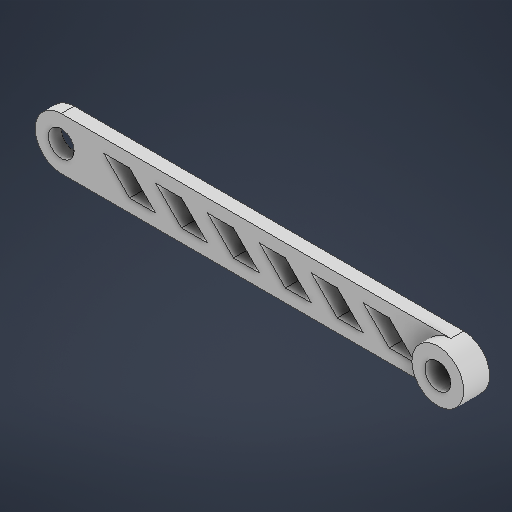
# Autodesk Inventor part: link2
Saved by Autodesk Inventor 2026.1 (Build 301233020, 233B)
## iProperties
Created: 2026-04-08
Part Number: link2
Material: Generic
Document SubType Name: Modeling
Designer: kadir
Density: 1 g/cm^3
Appearance: Default
Author: kadir
Autodesk Inventor part; units mm, degrees
ref_plane "YZ Plane" through (0, 0, 0) normal (1, 0, 0) x (0, 1, 0)
ref_plane "XZ Plane" through (0, 0, 0) normal (0, 1, 0) x (-1, 0, 0)
ref_plane "XY Plane" through (0, 0, 0) normal (0, 0, 1) x (1, 0, 0)
sketch "Sketch1" plane through (0, 0, 0) normal (0, 0, 1) x (1, 0, 0)
  circle A0 centre (0, 0) radius 5
  circle A1 centre (0, 0) radius 10
  circle A2 centre (150, 0) radius 5
  circle A3 centre (150, 0) radius 10
  line L0 (0, 10) -> (150, 10)
  line L1 (0, -10) -> (150, -10)
  line L2 (16.3209, 5) -> (26.3209, 5)
  line L3 (26.3209, 5) -> (36.3209, -5)
  line L4 (36.3209, -5) -> (26.3209, -5)
  line L5 (26.3209, -5) -> (16.3209, 5)
  line L6 (36.3209, 5) -> (46.3209, 5)
  line L7 (46.3209, 5) -> (56.3209, -5)
  line L8 (56.3209, -5) -> (46.3209, -5)
  line L9 (46.3209, -5) -> (36.3209, 5)
  line L10 (56.3209, 5) -> (66.3209, 5)
  line L11 (66.3209, 5) -> (76.3209, -5)
  line L12 (76.3209, -5) -> (66.3209, -5)
  line L13 (66.3209, -5) -> (56.3209, 5)
  line L14 (76.3209, 5) -> (86.3209, 5)
  line L15 (86.3209, 5) -> (96.3209, -5)
  line L16 (96.3209, -5) -> (86.3209, -5)
  line L17 (86.3209, -5) -> (76.3209, 5)
  line L18 (96.3209, 5) -> (106.3209, 5)
  line L19 (106.3209, 5) -> (116.3209, -5)
  line L20 (116.3209, -5) -> (106.3209, -5)
  line L21 (106.3209, -5) -> (96.3209, 5)
  line L22 (116.3209, 5) -> (126.3209, 5)
  line L23 (126.3209, 5) -> (136.3209, -5)
  line L24 (136.3209, -5) -> (126.3209, -5)
  line L25 (126.3209, -5) -> (116.3209, 5)
  dimension "d0" = 10
  dimension "d1" = 20
  dimension "d2" = 10
  dimension "d3" = 20
  dimension "d4" = 150
  dimension "d5" = 135
  dimension "d6" = 10
  dimension "d7" = 10
  dimension "d10" = 20
  constraints: 52 end point, 4 centre point, 4 horizontal, 4 point on circle, 3 coincident, 2 tangent, 1 horizontal alignment, 40 other
  measures "d0" diameter of A0
  measures "d1" diameter of A1
  measures "d2" diameter of A2
  measures "d3" diameter of A3
  measures "d4" distance of A2.centre point (0, 0)
  measures "d5" angle of L2 L3
  measures "d6" distance of L2.start L2.end
  measures "d7" distance of L3.end L4.end
  measures "d10" distance of L2.start L6.start
extrude "Extrusion1" add sketch "Sketch1" along normal blind 5 contours A1 | A1 L0 A3 L1
extrude "Extrusion2" add sketch "Sketch1" along normal blind 10 contours A3
body "Solid1"
